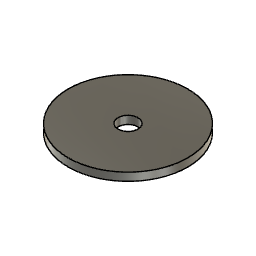
washer_2024-11-15 (Autodesk Fusion 360 design; units mm, degrees)
Autodesk Fusion 360 part; units mm, degrees
sketch "스케치1" plane through (0, 0, 0) normal (0, 0, 1) x (1, 0, 0)
  circle A0 centre (0, 0) radius 15
  circle A1 centre (0, 0) radius 2
  constraint coincident A0.centre A1.centre
extrude "돌출1" add sketch "스케치1" along normal blind 2
move_face "면 간격띄우기1" offset -0.5 1 faces at (1.9975, -0.0997, 1.3333)
